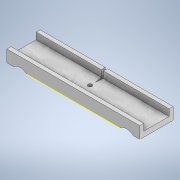
# Autodesk Inventor part: v2_gaura_pe_cant_la_9_mm
Saved by Autodesk Inventor 2022.6 (Build 266554000, 554)
## iProperties
Created: 2026-01-08
Part Number: v2_gaura_pe_cant_la_9_mm
Material: Generic
Document SubType Name: Modeling
Designer: Dragos Macovei
Density: 1 g/cm^3
Appearance: Default
Author: Dragos Macovei
Autodesk Inventor part; units mm, degrees
ref_plane "YZ Plane" through (0, 0, 0) normal (1, 0, 0) x (0, 1, 0)
ref_plane "XZ Plane" through (0, 0, 0) normal (0, 1, 0) x (-1, 0, 0)
ref_plane "XY Plane" through (0, 0, 0) normal (0, 0, 1) x (1, 0, 0)
sketch "Sketch1" plane through (0, 0, 0) normal (0, 1, 0) x (-1, 0, 0)
  line L0 (0, 0) -> (100, 0)
  line L1 (100, 0) -> (100, 25)
  line L2 (100, 25) -> (0, 25)
  line L3 (0, 25) -> (0, 0)
  dimension "d0" = 100
  dimension "d1" = 25
  constraints: 8 end point, 2 parallel, 1 horizontal, 1 perpendicular
  measures "d0" distance of L2.end L1.end
  measures "d1" distance of L1.end L0.end
extrude "Extrusion1" add sketch "Sketch1" along normal blind 4
sketch "Sketch2" plane through (0, 4, 0) normal (0, 1, 0) x (1, 0, 0)
  line L0 (-100, 0) -> (-100, -25) projected
  line L1 (0, -25) -> (0, 0) projected
  line L2 (-100, -25) -> (0, -25)
  line L3 (0, -25) -> (0, -22)
  line L4 (0, -22) -> (-100, -22)
  line L5 (-100, -22) -> (-100, -25)
  line L6 (-100, 0) -> (0, 0)
  line L7 (0, 0) -> (0, -3)
  line L8 (0, -3) -> (-100, -3)
  line L9 (-100, -3) -> (-100, 0)
  line L10 (0, 0) -> (-100, 0) projected
  point P0 (0, -25)
  dimension "d4" = 3
  dimension "d5" = 3
  dimension "d6" = 0
  constraints: 16 end point, 4 parallel, 3 point on line, 2 horizontal, 2 perpendicular
  measures "d4" distance between parallel lines of L2 L4
  measures "d5" distance between parallel lines of L6 L8
  measures "d6" distance between parallel lines of L10 L6
extrude "Extrusion2" add sketch "Sketch2" along normal blind 5 contours L6 L1 L8 L0 | L4 L1 L2 L0
sketch "Sketch3" plane through (0, 0, 0) normal (0, -1, 0) x (1, 0, 0)
  line L0 (-100, 0) -> (-100, 25) construction
  line L1 (0, 0) -> (-100, 0) construction
  line L2 (0, 25) -> (0, 0) construction
  line L3 (-100, 25) -> (0, 25) construction
  line L4 (-100, 25) -> (0, 25) construction
  line L5 (-100, 0) -> (-100, 25) construction
  line L6 (0, 25) -> (-100, 0) construction
  line L7 (-100, 0) -> (-100, 25) construction
  line L8 (-100, 25) -> (0, 0) construction
  circle A0 centre (-50, 12.5) radius 5
  circle A1 centre (-50, 12.5) radius 1.5
  dimension "d11" = 10
  dimension "d12" = 3
  constraints: 6 end point, 2 centre point, 1 coincident, 1 collinear, 1 midpoint
  measures "d11" diameter of A0
  measures "d12" diameter of A1
extrude "Extrusion3" add sketch "Sketch3" along normal blind 7
fillet "Fillet3" radius 4 1 edges at (-55, 0, 12.5)
sketch "Sketch4" plane through (-50, -7, 12.5) normal (0, -1, 0) x (1, 0, 0)
  circle A0 centre (0, 0) radius 1.5
  point P0 (50, -12.5)
  constraints: 1 centre point
extrude "Extrusion4" cut sketch "Sketch4" against normal through all
sketch "Sketch5" plane through (0, 0, 0) normal (0, -1, 0) x (1, 0, 0)
  point P0 (0, 0)
sketch "Sketch6" plane through (-100, 0, 25) normal (0, 0, 1) x (1, 0, 0)
  line L0 (0, 0) -> (100, 0) projected
  line L1 (100, 0) -> (100, 9) projected
  arc A0 (95, 0) -> (85, 0) centre (90, -5.25) ccw
  arc A1 (15, 0) -> (5, 0) centre (10, -5.25) ccw
  point P0 (100, 0)
  point P1 (90, 0)
  point P2 (10, 0)
  point P3 (90, 2)
  point P4 (10, 2)
  dimension "d18" = 10
  dimension "d19" = 10
  dimension "d20" = 5
  dimension "d21" = 5
  dimension "d22" = 5
  dimension "d23" = 5
  dimension "d24" = 2
  dimension "d25" = 2
  constraints: 6 point on circle, 6 point on line, 2 centre point, 2 coincident
  measures "d18" distance of point (90, 0) L0.end
  measures "d19" distance of L0.start point (10, 0)
  measures "d20" distance of A1.start point (10, 0)
  measures "d21" distance of A1.end point (10, 0)
  measures "d22" distance of A0.end point (90, 0)
  measures "d23" distance of A0.start point (90, 0)
  measures "d24" distance of point (90, 2) point (90, 0)
  measures "d25" distance from line of L0 point (10, 2)
extrude "Extrusion5" cut sketch "Sketch6" against normal through all
sketch "Sketch7" plane through (-100, 9, 25) normal (0, 0, 1) x (1, 0, 0)
  point P0 (100, -9)
sketch "Sketch8" plane through (0, 0, 0) normal (0, -1, 0) x (1, 0, 0)
  circle A0 centre (-50, 12.5) radius 9 projected
  line L0 (-85, 25) -> (-85, 0) projected
  line L1 (-15, 0) -> (-85, 0) projected
  line L2 (-15, 0) -> (-15, 25) projected
  line L3 (-85, 25) -> (-15, 25) projected
  point P0 (0, 0)
sketch "Sketch9" plane through (0, 0, 0) normal (0, -1, 0) x (1, 0, 0)
  circle A0 centre (-50, 12.5) radius 1.5 projected
  line L0 (-50, 12.5) -> (-50, 0.5)
  line L1 (-50, 0.5) -> (-49.134, 0)
  line L2 (-15, 0) -> (-85, 0) projected
  line L3 (-49.134, 0) -> (-51.134, 0)
  line L4 (-51.134, 0) -> (-50, 3.5)
  circle A1 centre (-50, 12.5) radius 9 projected
  line L5 (-49.134, 0) -> (-50, 3.5)
  line L6 (-51.134, 0) -> (-50, 8.3784)
  line L7 (-49.134, 0) -> (-50, 8.3784)
  point P0 (0, 0)
  point P1 (-85, 0)
  dimension "d28" = 1
  dimension "d29" = 2
  constraints: 14 end point, 2 point on line, 1 vertical, 1 vertical alignment, 4 other
  measures "d28" distance of L0.end L1.end
  measures "d29" distance of L1.end L3.end
extrude "Extrusion6" cut sketch "Sketch9" along normal through all both and the other way through all contours L7 A1 L0 | L0 A1 L6 | L5 L1 L0 | L0 L1 L2 L4 | L4 L6 A1 | A1 L7 L5
body "Solid1"
